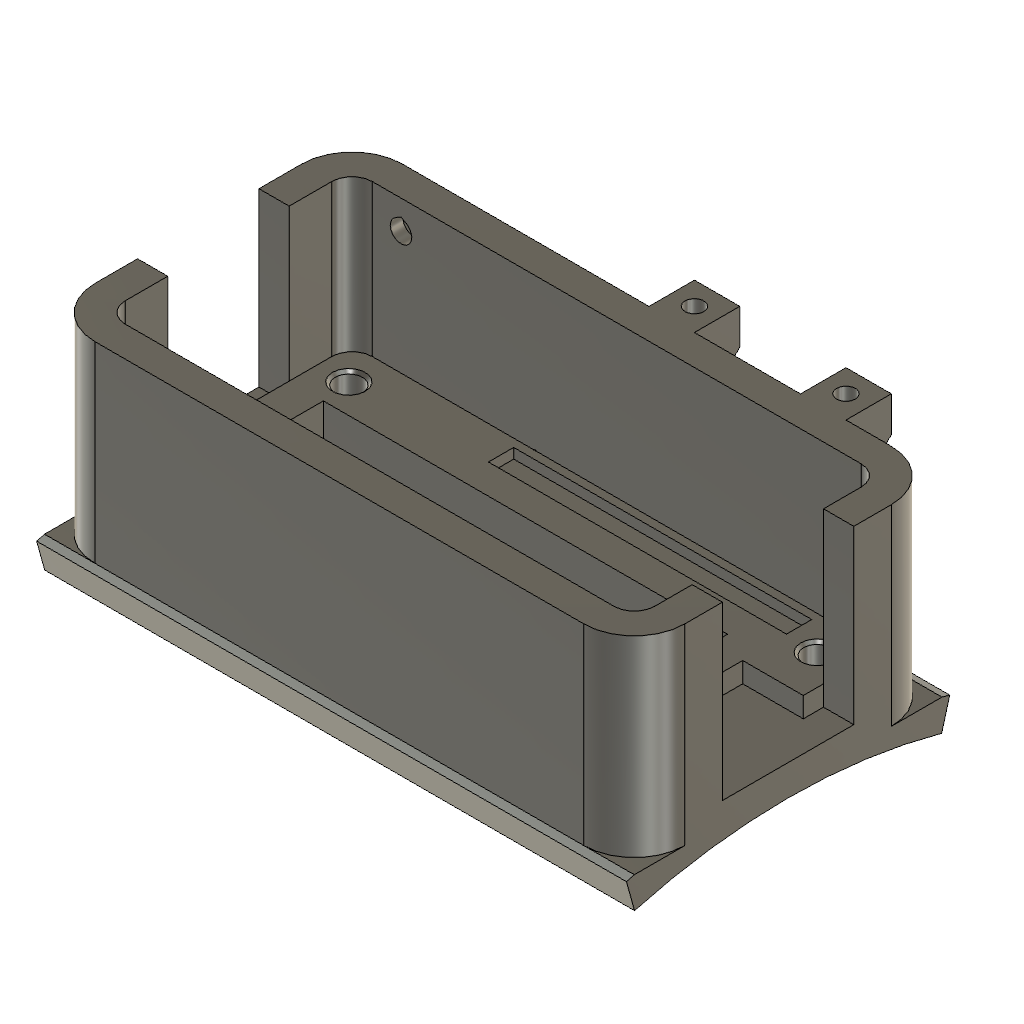
Subi CAN Box Mount (Autodesk Fusion 360 design; units mm, degrees)
part number: 2026-09-13-18-25-52-503
Autodesk Fusion 360 part; units mm, degrees
sketch "Sketch1" plane through (0, 0, 0) normal (0, 0, 1) x (1, 0, 0)
  line L0 (25.4, 11.43) -> (-25.4, 11.43) construction
  line L1 (-25.4, 11.43) -> (-25.4, -11.43) construction
  line L2 (-25.4, -11.43) -> (25.4, -11.43) construction
  line L3 (25.4, -11.43) -> (25.4, 11.43) construction
  line L4 (25.4, 11.43) -> (-25.4, -11.43) construction
  line L5 (-25.4, 11.43) -> (25.4, -11.43) construction
  line L6 (26.1937, 12.2237) -> (-26.1938, 12.2238)
  line L7 (-26.1938, 12.2238) -> (-26.1938, -12.2237)
  line L8 (-26.1938, -12.2237) -> (26.1937, -12.2237)
  line L9 (26.1937, -12.2237) -> (26.1937, 12.2238)
  line L10 (23.1775, 8.89) -> (-23.1775, 8.89) construction
  line L11 (-23.1775, 8.89) -> (-23.1775, -8.89) construction
  line L12 (-23.1775, -8.89) -> (23.1775, -8.89) construction
  line L13 (23.1775, -8.89) -> (23.1775, 8.89) construction
  line L14 (23.1775, 8.89) -> (-23.1775, -8.89) construction
  line L15 (-23.1775, 8.89) -> (23.1775, -8.89) construction
  line L16 (-29.1938, -15.2237) -> (29.1937, -15.2237)
  line L17 (29.1937, -15.2237) -> (29.1937, 15.2237)
  line L18 (29.1937, 15.2238) -> (-29.1938, 15.2238)
  line L19 (-29.1938, 15.2238) -> (-29.1938, -15.2238)
  line L20 (-29.1938, 6) -> (-26.1938, 6)
  line L21 (-29.1938, -6) -> (-26.1938, -6)
  line L22 (26.1937, 6.5) -> (29.1937, 6.5)
  line L23 (26.1937, -6.5) -> (29.1937, -6.5)
  line L24 (26.1937, 4.5) -> (20.1937, 4.5)
  line L25 (20.1937, 4.5) -> (20.1937, -4.5)
  line L26 (20.1937, -4.5) -> (26.1937, -4.5)
  circle A0 centre (-23.1775, 8.89) radius 1.25
  circle A1 centre (23.1775, 8.89) radius 1.25
  circle A2 centre (23.1775, -8.89) radius 1.25
  circle A3 centre (-23.1775, -8.89) radius 1.25
  dimension "d1" = 50.8
  dimension "d2" = 22.86
  dimension "d3" = 0.7937
  dimension "d4" = 46.355
  dimension "d5" = 17.78
  dimension "d6" = 3
  dimension "d11" = 12
  dimension "d12" = 6
  dimension "d41" = 6
  dimension "d44" = 9
  dimension "d45" = 4.5
  dimension "d46" = 13
  dimension "d47" = 6.5
  dimension "d50" = 2.5
  dimension "d51" = 2.5
  dimension "d52" = 2.5
  dimension "d53" = 2.5
  constraint horizontal L0
  constraint perpendicular L0 L1
  constraint parallel L0 L2
  constraint parallel L1 L3
  constraint coincident L4 origin
  constraint coincident L5 origin
  constraint horizontal L10
  constraint perpendicular L10 L11
  constraint parallel L10 L12
  constraint parallel L11 L13
  constraint coincident L14 origin
  constraint coincident L15 origin
  constraint coincident L19 L20.start
  constraint coincident L7 L20.end
  constraint perpendicular L7 L20
  constraint coincident L19 L21.start
  constraint coincident L7 L21.end
  constraint perpendicular L7 L21
  constraint coincident L9 L22.start
  constraint coincident L17 L22.end
  constraint perpendicular L17 L22
  constraint coincident L17 L23.end
  constraint perpendicular L17 L23
  constraint coincident L9 L24.start
  constraint perpendicular L9 L24
  constraint perpendicular L24 L25
  constraint coincident L9 L26.end
  constraint perpendicular L9 L26
  constraint coincident L10.end L11.start
  constraint coincident L10.start L13.end
  constraint coincident L12.end L13.start
  constraint coincident L11.end L12.start
  constraint coincident L9 L23.start
  measures "d1" distance of L0.start L0.end
  measures "d2" distance of L0.start L2.end
  measures "d4" distance of L10.start L10.end
  measures "d5" distance of L10.start L12.end
  measures "d11" distance of L20 L21
  measures "d12" distance of origin L20
  measures "d41" distance of L24.start L24.end
  measures "d44" distance of L24 L26
  measures "d45" distance of origin L24
  measures "d46" distance of L22 L23
  measures "d47" distance of origin L22
  measures "d50" diameter of A0
  measures "d51" diameter of A1
  measures "d52" diameter of A2
  measures "d53" diameter of A3
extrude "Extrude1" add sketch "Sketch1" against normal blind 4 contours L6 L7 L8 L9 L24 L25 L26 | L6 L7 L9 L17 L18 L19 L20 L22 | L9 L17 L22 L23 | L7 L19 L20 L21 | L9 L24 L25 L26 | L7 L8 L9 L16 L17 L19 L21 L23 | A0 | A1 | A2 | A3
extrude "Extrude4" cut sketch "Sketch1" against normal blind 2 contours L9 L17 L22 L23 | L7 L19 L20 L21 | L9 L24 L25 L26
extrude "Extrude6" add sketch "Sketch1" along normal blind 15 contours L6 L7 L9 L17 L18 L19 L20 L22 | L7 L8 L9 L16 L17 L19 L21 L23
hole "Hole1" at (-23.1775, 8.89, 0) at (-23.1775, -8.89, 0) at (23.1775, -8.89, 0) at (23.1775, 8.89, 0) direction (0, 0, -1) diameter 2.7 depth 4 tip angle 180 countersink diameter 3.25 countersink angle 90
sketch "Sketch2" plane through (0, 0, 0) normal (0, 0, 1) x (1, 0, 0)
  line L0 (-9.4, 11.43) -> (20.1, 11.43)
  line L1 (20.1, 11.43) -> (20.1, 8.93)
  line L2 (20.1, 8.93) -> (-9.4, 8.93)
  line L3 (-9.4, 8.93) -> (-9.4, 11.43)
  line L4 (-20.25, -8.93) -> (20.25, -8.93)
  line L5 (20.25, -8.93) -> (20.25, -11.43)
  line L6 (20.25, -11.43) -> (-20.25, -11.43)
  line L7 (-20.25, -11.43) -> (-20.25, -8.93)
  line L8 (-25.4, 11.43) -> (-25.4, -11.43)
  line L9 (25.4, 11.43) -> (-25.4, 11.43)
  line L10 (-25.4, -11.43) -> (25.4, -11.43)
  line L11 (25.4, -11.43) -> (25.4, 11.43)
  line L12 (0, -8.93) -> (0, 0) construction
  dimension "d33" = 2.5
  dimension "d34" = 2.5
  dimension "d35" = 40.5
  dimension "d37" = 16
  dimension "d38" = 29.5
  constraint horizontal L0
  constraint vertical L1
  constraint horizontal L2
  constraint vertical L3
  constraint horizontal L4
  constraint vertical L5
  constraint horizontal L6
  constraint vertical L7
  constraint midpoint L4 L12.start
  constraint coincident L12.end origin
  constraint vertical L12
  constraint coincident L6 L10.end
  constraint coincident L0 L9.start
  measures "d33" distance of L0.start L2.end
  measures "d34" distance of L4.end L5.end
  measures "d35" distance of L5.end L6.end
  measures "d37" distance of L3 L8
  measures "d38" distance of L1.end L2.end
extrude "Extrude5" cut sketch "Sketch2" against normal blind 1 contours L0 L1 L2 L3 L9 | L4 L5 L6 L7 L10
fillet "Fillet3" radius 2 4 edges at (-26.1938, 12.2238, 7.5) (-26.1938, -12.2237, 7.5) (26.1937, 12.2238, 7.5) (26.1937, -12.2237, 7.5)
fillet "Fillet4" radius 5 4 edges at (29.1937, 15.2238, 5.5) (29.1937, -15.2237, 5.5) (-29.1938, 15.2238, 5.5) (-29.1938, -15.2238, 5.5)
sketch "Sketch4" plane through (0, 0, 0) normal (0, 0, 1) x (1, 0, 0)
  line L0 (-22.8063, 6) -> (17.1937, 6)
  line L1 (17.1937, 6) -> (17.1937, -6)
  line L2 (17.1937, -6) -> (-22.8063, -6)
  line L3 (-22.8063, -6) -> (-22.8063, 6)
  point P0 (-26.1938, 6)
  point P1 (20.1937, 4.5)
  dimension "d95" = 12
  dimension "d97" = 3
  dimension "d98" = 3.3875
  dimension "d99" = 6
  constraint horizontal L0
  constraint vertical L1
  constraint horizontal L2
  constraint vertical L3
  measures "d95" distance of L0.end L1.end
  measures "d97" distance of L1 P1
  measures "d98" distance of L0.start P0
  measures "d99" distance of origin L0
extrude "Extrude13" cut sketch "Sketch4" against normal blind 4
sketch "Sketch6" plane through (0, 15.2238, 0) normal (0, 1, 0) x (-1, 0, 0)
  line L0 (24.1938, -4) -> (24.1938, 15)
  line L1 (24.1938, 15) -> (-24.1937, 15)
  line L2 (-24.1937, 15) -> (-24.1937, -4)
  line L3 (-24.1937, -4) -> (24.1938, -4)
  line L4 (5.6938, 14.5) -> (23.6938, 14.5) construction
  line L5 (23.6938, 14.5) -> (23.6938, -3.5) construction
  line L6 (23.6938, -3.5) -> (5.6938, -3.5) construction
  line L7 (5.6938, -3.5) -> (5.6938, 14.5) construction
  line L8 (5.6938, -3.5) -> (23.6938, 14.5) construction
  line L9 (23.3688, 13.3191) -> (21.3438, 14.4883)
  line L10 (21.3438, 14.4883) -> (19.3188, 13.3191)
  line L11 (19.3188, 13.3191) -> (19.3188, 10.9809)
  line L12 (19.3188, 10.9809) -> (21.3438, 9.8117)
  line L13 (21.3438, 9.8117) -> (23.3688, 10.9809)
  line L14 (23.3688, 10.9809) -> (23.3688, 13.3191)
  line L15 (10.0688, 0.0191) -> (8.0438, 1.1883)
  line L16 (8.0438, 1.1883) -> (6.0188, 0.0191)
  line L17 (6.0188, 0.0191) -> (6.0188, -2.3191)
  line L18 (6.0188, -2.3191) -> (8.0438, -3.4883)
  line L19 (8.0438, -3.4883) -> (10.0688, -2.3191)
  line L20 (10.0688, -2.3191) -> (10.0688, 0.0191)
  circle A0 centre (21.3438, 12.15) radius 1.0625
  circle A1 centre (8.0438, -1.15) radius 1.0625
  line L21 (20.8125, 13.0702) -> (21.3438, 13.3769)
  line L22 (21.3438, 13.3769) -> (21.875, 13.0702)
  line L23 (7.5125, -0.2298) -> (8.0438, 0.0769)
  line L24 (8.0438, 0.0769) -> (8.575, -0.2298)
  point P0 (21.3438, 12.15)
  point P1 (8.0438, -1.15)
  dimension "d104" = 18
  dimension "d105" = 18
  dimension "d106" = 0.5
  dimension "d107" = 0.5
  dimension "d109" = 4.05
  dimension "d110" = 4.05
  dimension "d111" = 2.35
  dimension "d112" = 2.35
  dimension "d113" = 2.125
  dimension "d114" = 2.125
  constraint horizontal L4
  constraint vertical L5
  constraint horizontal L6
  constraint vertical L7
  constraint coincident L8 P0
  constraint coincident L8 P1
  constraint vertical L14
  constraint vertical L20
  constraint coincident P0 A0.centre
  constraint coincident P1 A1.centre
  constraint coincident A0 L21.start
  constraint coincident A0 L22.end
  constraint tangent A0 L22
  constraint parallel L9 L22
  constraint parallel L10 L21
  constraint vertical L9.end L21.end
  constraint coincident A1 L23.start
  constraint coincident A1 L24.end
  constraint parallel L15 L24
  constraint parallel L16 L23
  constraint vertical L15.end L23.end
  constraint tangent A1 L24
  measures "d104" distance of L4.start L4.end
  measures "d105" distance of L4.end L5.end
  measures "d106" distance of L1 L4
  measures "d107" distance of L0 L5
  measures "d109" distance of L11 L14
  measures "d110" distance of L17 L20
  measures "d111" distance of L4 P0
  measures "d112" distance of L7 P1
  measures "d113" diameter of A0
  measures "d114" diameter of A1
extrude "Extrude14" cut sketch "Sketch6" against normal blind 1.75 contours L9 L10 L11 L12 L13 L14 | L15 L16 L17 L18 L19 L20 | A0 | A0 L21 L22 | A1 | A1 L23 L24
extrude "Extrude15" cut sketch "Sketch6" against normal blind 3 contours A0 | A0 L21 L22 | A1 | A1 L23 L24
sketch "Sketch7" plane through (29.1937, 0, 0) normal (1, 0, 0) x (0, 1, 0)
  line L0 (-10.2237, 15) -> (-10.2237, -4)
  line L1 (-10.2237, -4) -> (10.2237, -4)
  line L2 (10.2237, -4) -> (10.2237, 15)
  line L3 (10.2237, 15) -> (6.5, 15)
  line L4 (6.5, 15) -> (6.5, -2)
  line L5 (6.5, -2) -> (-6.5, -2)
  line L6 (-6.5, -2) -> (-6.5, 15)
  line L7 (-6.5, 15) -> (-10.2237, 15)
  arc A0 (16, -4.2092) -> (-16, -4.2092) centre (0, -62.0365) ccw
  arc A1 (15.2, -7.1006) -> (-15.2, -7.1006) centre (0, -62.0365) ccw
  line L8 (-15.2, -7.1006) -> (-16, -4.2092)
  line L9 (15.2, -7.1006) -> (16, -4.2092)
  line L10 (-15.2237, -4) -> (15.2237, -4)
  point P0 (15.2238, -4)
  point P1 (-15.2237, -4)
  dimension "d119" = 60
  dimension "d120" = 16
  dimension "d121" = 16
  dimension "d122" = -3
  constraint vertical origin A0.centre
  constraint coincident A0 P0
  constraint perpendicular A0 L8
  constraint perpendicular A0 L9
  constraint coincident P1 L10.start
  measures "d119" radius of A0
  measures "d120" horizontal distance of origin A0.start
  measures "d121" horizontal distance of origin A0.end
extrude "Extrude16" add sketch "Sketch7" against normal up to surface (58.3875 mm away) contours L1 A0 A1 L8 L9 L10
sketch "Sketch8" plane through (0, 0, 15) normal (0, 0, 1) x (-1, 0, 0)
  arc A0 (24.1938, -15.2238) -> (29.1938, -10.2238) centre (24.1937, -10.2237) ccw
  line L0 (29.1938, -10.2238) -> (29.1938, -6)
  line L1 (29.1938, -6) -> (26.1938, -6)
  line L2 (26.1938, -6) -> (26.1938, -10.2238)
  arc A1 (24.1938, -12.2238) -> (26.1937, -10.2238) centre (24.1937, -10.2237) ccw
  line L3 (24.1938, -12.2238) -> (-24.1937, -12.2238)
  arc A2 (-26.1937, -10.2238) -> (-24.1937, -12.2238) centre (-24.1937, -10.2238) ccw
  line L4 (-26.1937, -10.2238) -> (-26.1937, -6.5)
  line L5 (-26.1937, -6.5) -> (-29.1937, -6.5)
  line L6 (-29.1937, -6.5) -> (-29.1937, -10.2237)
  arc A3 (-29.1937, -10.2237) -> (-24.1937, -15.2238) centre (-24.1937, -10.2238) ccw
  line L7 (-24.1937, -15.2237) -> (24.1938, -15.2238)
  line L8 (-19.6937, -15.2238) -> (-15.1937, -15.2238)
  line L9 (-15.1937, -15.2238) -> (-15.1937, -19.7238)
  line L10 (-15.1937, -19.7238) -> (-19.6938, -19.7238)
  line L11 (-19.6937, -19.7238) -> (-19.6937, -15.2237)
  line L12 (-4.6937, -15.2238) -> (-0.1937, -15.2238)
  line L13 (-0.1937, -15.2238) -> (-0.1937, -19.7238)
  line L14 (-0.1937, -19.7238) -> (-4.6937, -19.7238)
  line L15 (-4.6937, -19.7238) -> (-4.6937, -15.2237)
  circle A4 centre (-2.4437, -17.4738) radius 0.925
  circle A5 centre (-17.4438, -17.4738) radius 0.925
  line L16 (-17.4438, -17.4738) -> (-17.4437, -19.7238) construction
  line L17 (-17.4438, -17.4738) -> (-15.1937, -17.4738) construction
  line L18 (-2.4437, -17.4738) -> (-2.4437, -19.7238) construction
  dimension "d125" = 4.5
  dimension "d126" = 4.5
  dimension "d127" = 4.5
  dimension "d128" = 4.5
  dimension "d129" = 19.5
  dimension "d130" = 4.5
  dimension "d133" = 1.85
  dimension "d134" = 1.85
  constraint horizontal L8
  constraint vertical L9
  constraint horizontal L10
  constraint vertical L11
  constraint coincident L7 L8.start
  constraint horizontal L12
  constraint vertical L13
  constraint horizontal L14
  constraint vertical L15
  constraint coincident L7 L12.start
  constraint coincident A5.centre L16.start
  constraint midpoint L10 L16.end
  constraint midpoint L9 L17.end
  constraint coincident A4.centre L18.start
  constraint midpoint L14 L18.end
  constraint vertical L16
  constraint horizontal L17
  constraint horizontal A4.centre A5.centre
  constraint vertical L18
  measures "d125" distance of L9.end L11.start
  measures "d126" distance of L8.end L9.end
  measures "d127" distance of L12.end L13.end
  measures "d128" distance of L13.end L14.end
  measures "d129" distance of L11 L13
  measures "d130" distance of L7.start L8.start
  measures "d133" diameter of A4
  measures "d134" diameter of A5
extrude "Extrude17" add sketch "Sketch8" against normal blind 8 contours L7 L12 L13 L14 L15 | L7 L8 L9 L10 L11
draft "Draft1" angle 45 neutral plane through (29.1937, 15.2237, 0) pull (0, 1, 0) 2 faces at (2.4668, 19.2812, 7) (17.4207, 19.2812, 7)
equation "d3 = ( 0.125 / 4 ) * 1 in"
equation "d6 = thickness"
equation "d12 = 12 mm / 2"
equation "d26 = ( 3 * 0.9 ) * 1 mm"
equation "d59 = 2 mm + thickness"
equation "thickness = 3 mm"
equation "d117 = -thickness"
